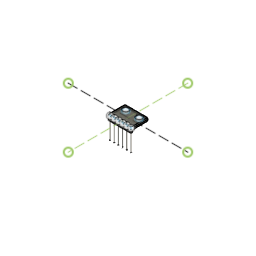
BMP280 v2 (Autodesk Fusion 360 design; units mm, degrees)
Autodesk Fusion 360 part; units mm, degrees
sketch "草图1" plane through (0, 0, 0) normal (0, 0, 1) x (1, 0, 0)
  line L0 (-7.5, 5.5) -> (7.5, 5.5)
  line L1 (7.5, 5.5) -> (7.5, -5.5)
  line L2 (7.5, -5.5) -> (-7.5, -5.5)
  line L3 (-7.5, -5.5) -> (-7.5, 5.5)
  line L4 (0, 40) -> (0, -40) construction
  line L5 (-40, 0) -> (40, 0) construction
  circle A0 centre (-4.5, 3) radius 2
  circle A1 centre (4.5, 3) radius 2
  circle A2 centre (7, -5) radius 0.25
  circle A3 centre (4.2, -5) radius 0.25
  circle A4 centre (1.4, -5) radius 0.25
  circle A5 centre (-1.4, -5) radius 0.25
  circle A6 centre (-4.2, -5) radius 0.25
  circle A7 centre (-7, -5) radius 0.25
  line L6 (-7.5, -5.5) -> (7.5, -5.5)
  line L7 (7.5, -5.5) -> (7.5, -4.5)
  line L8 (7.5, -4.5) -> (-7.5, -4.5)
  line L9 (-7.5, -4.5) -> (-7.5, -5.5)
  dimension "d1" = 15
  dimension "d2" = 11
  dimension "d3" = 4
  dimension "d4" = 4
  dimension "d10" = 0.5
  dimension "d13" = -14
  dimension "d14" = 0
  constraint horizontal L0
  constraint vertical L1
  constraint horizontal L2
  constraint vertical L3
  constraint perpendicular L2 L4
  constraint perpendicular L3 L5
  constraint symmetric L0 L2 L5
  constraint symmetric L1 L3 L4
  constraint horizontal L6
  constraint vertical L7
  constraint horizontal L8
  constraint vertical L9
  constraint coincident L1 L7.end
  measures "d1" distance of L1.end L2.end
  measures "d2" distance of L0.end L1.end
  measures "d3" diameter of A0
  measures "d4" diameter of A1
  measures "d10" diameter of A2
extrude "拉伸1" add sketch "草图1" along normal mid plane 2 makes body 1
extrude "拉伸2" add sketch "草图1" along normal blind 2 separate body contours A7 makes body 2
extrude "拉伸3" add sketch "草图1" against normal blind 14 separate body contours A7 makes body 3
extrude "拉伸4" add sketch "草图1" along normal blind 2 separate body contours A6 makes body 4
extrude "拉伸5" add sketch "草图1" against normal blind 14 separate body contours A6 makes body 5
extrude "拉伸6" add sketch "草图1" along normal blind 2 separate body contours A5 makes body 6
extrude "拉伸7" add sketch "草图1" against normal blind 14 separate body contours A5 makes body 7
extrude "拉伸8" add sketch "草图1" along normal blind 2 separate body contours A4 makes body 8
extrude "拉伸9" add sketch "草图1" against normal blind 14 separate body contours A4 makes body 9
extrude "拉伸10" add sketch "草图1" along normal blind 2 separate body contours A3 makes body 10
extrude "拉伸11" add sketch "草图1" against normal blind 14 separate body contours A3 makes body 11
extrude "拉伸12" add sketch "草图1" along normal blind 2 separate body contours A2 makes body 12
extrude "拉伸13" add sketch "草图1" against normal blind 14 separate body contours A2 makes body 13
sketch "草图2" plane through (0, 0, -1) normal (0, 0, -1) x (1, 0, 0)
  circle A0 centre (4.5, -3) radius 2
  circle A1 centre (-4.5, -3) radius 2
  circle A2 centre (-1.4, 5) radius 0.25
  circle A3 centre (-7, 5) radius 0.25
  circle A4 centre (-4.2, 5) radius 0.25
  circle A5 centre (4.2, 5) radius 0.25
  circle A6 centre (7, 5) radius 0.25
  circle A7 centre (1.4, 5) radius 0.25
  line L0 (7.5, 5.5) -> (-7.5, 5.5)
  line L1 (-7.5, 5.5) -> (-7.5, -5.5)
  line L2 (-7.5, -5.5) -> (7.5, -5.5)
  line L3 (7.5, -5.5) -> (7.5, 5.5)
  line L4 (-7.5, 5.5) -> (7.5, 5.5)
  line L5 (7.5, 5.5) -> (7.5, 4.5)
  line L6 (7.5, 4.5) -> (-7.5, 4.5)
  line L7 (-7.5, 4.5) -> (-7.5, 5.5)
  constraint horizontal L4
  constraint vertical L5
  constraint horizontal L6
  constraint vertical L7
  constraint coincident L3 L5.end
  constraint coincident L0.end L1.start
extrude "拉伸14" add sketch "草图2" along normal blind 1.5 contours L0 L1 L3 L4 L5 L6 L7 bodies 1 3 5 7 9 11 13
